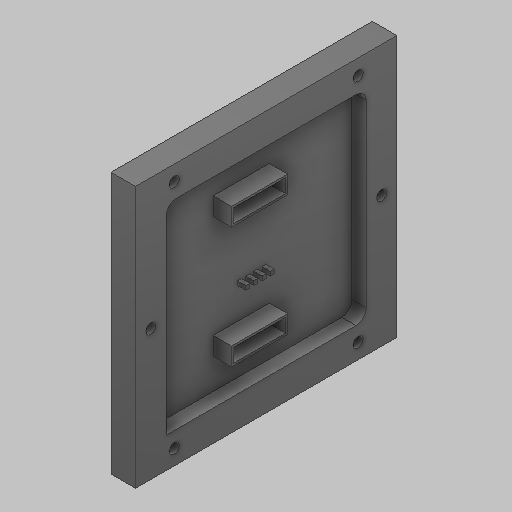
# Autodesk Inventor part: Pantalla_Led_B
Saved by Autodesk Inventor 2027 (Build 310192000, 192)
## iProperties
Created: 2026-11-23
Part Number: Pantalla_Led_B
Material: Genérico
Document SubType Name: Modeling
Designer: Alexander
Density: 1 g/cm^3
Appearance: Valor por defecto
Author: Alexander
Autodesk Inventor part; units mm, degrees
ref_plane "YZ Plane" through (0, 0, 0) normal (1, 0, 0) x (0, 1, 0)
ref_plane "XZ Plane" through (0, 0, 0) normal (0, 1, 0) x (-1, 0, 0)
ref_plane "XY Plane" through (0, 0, 0) normal (0, 0, 1) x (1, 0, 0)
sketch "Boceto1" plane through (0, 0, 0) normal (1, 0, 0) x (0, 1, 0)
  circle A0 centre (56.5, 45) radius 1.5
  circle A1 centre (-56.5, 45) radius 1.5
  circle A2 centre (-56.5, -45) radius 1.5
  circle A3 centre (56.5, -45) radius 1.5
  line L0 (64, 64) -> (-64, 64)
  line L1 (-64, 64) -> (-64, -64)
  line L2 (-64, -64) -> (64, -64)
  line L3 (64, -64) -> (64, 64)
  line L4 (44, 49) -> (-49, 49)
  line L5 (-49, 49) -> (-49, -44)
  line L6 (-44, -49) -> (44, -49)
  line L7 (49, -44) -> (49, 44)
  arc A4 (49, 44) -> (44, 49) centre (44, 44) ccw
  arc A5 (44, -49) -> (49, -44) centre (44, -44) ccw
  arc A6 (-49, -44) -> (-44, -49) centre (-44, -44) ccw
  circle A7 centre (0, 56.5) radius 1.5
  circle A8 centre (0, -56.5) radius 1.5
  circle A9 centre (56.5, 45) radius 2.5
  circle A10 centre (56.5, -45) radius 2.5
  circle A11 centre (0, -56.5) radius 2.5
  circle A12 centre (-56.5, -45) radius 2.5
  circle A13 centre (-56.5, 45) radius 2.5
  circle A14 centre (0, 56.5) radius 2.5
  line L8 (-25.2, 19) -> (-34, 19)
  line L9 (-34, 19) -> (-34, -8.5)
  line L10 (-34, -8.5) -> (-25.2, -8.5)
  line L11 (-25.2, -8.5) -> (-25.2, 19)
  line L12 (34, 19) -> (25.2, 19)
  line L13 (25.2, 19) -> (25.2, -8.5)
  line L14 (25.2, -8.5) -> (34, -8.5)
  line L15 (34, -8.5) -> (34, 19)
  line L16 (-4.8656, 9.0356) -> (-13.1244, 9.0356)
  line L17 (-13.1244, 9.0356) -> (-13.1244, -8.9644)
  line L18 (-13.1244, -8.9644) -> (-4.8656, -8.9644)
  line L19 (-4.8656, -8.9644) -> (-4.8656, 9.0356)
  line L20 (33, -7.5) -> (26.2, -7.5)
  line L21 (26.2, -7.5) -> (26.2, 18)
  line L22 (26.2, 18) -> (33, 18)
  line L23 (33, 18) -> (33, -7.5)
  line L24 (-26.2, -7.5) -> (-33, -7.5)
  line L25 (-33, -7.5) -> (-33, 18)
  line L26 (-33, 18) -> (-26.2, 18)
  line L27 (-26.2, 18) -> (-26.2, -7.5)
  line L28 (-8.0495, -6.9644) -> (-10.0495, -6.9644)
  line L29 (-10.0495, -6.9644) -> (-10.0495, -4.9644)
  line L30 (-10.0495, -4.9644) -> (-8.0495, -4.9644)
  line L31 (-8.0495, -4.9644) -> (-8.0495, -6.9644)
  line L32 (-8.0495, -2.9644) -> (-10.0495, -2.9644)
  line L33 (-10.0495, -2.9644) -> (-10.0495, -0.9644)
  line L34 (-10.0495, -0.9644) -> (-8.0495, -0.9644)
  line L35 (-8.0495, -0.9644) -> (-8.0495, -2.9644)
  line L36 (-8.0495, 1.0356) -> (-10.0495, 1.0356)
  line L37 (-10.0495, 1.0356) -> (-10.0495, 3.0356)
  line L38 (-10.0495, 3.0356) -> (-8.0495, 3.0356)
  line L39 (-8.0495, 3.0356) -> (-8.0495, 1.0356)
  line L40 (-8.0495, 5.0356) -> (-10.0495, 5.0356)
  line L41 (-10.0495, 5.0356) -> (-10.0495, 7.0356)
  line L42 (-10.0495, 7.0356) -> (-8.0495, 7.0356)
  line L43 (-8.0495, 7.0356) -> (-8.0495, 5.0356)
  point P0 (0, 0)
  point P1 (0, 0)
  point P2 (-49, 49)
  point P3 (49, 49)
  point P4 (49, -49)
  point P5 (-49, -49)
  point P6 (-8.995, -8.9644)
  point P7 (-9.0495, -0.9644)
  point P8 (-9.0495, -4.9644)
  dimension "d0" = 3
  dimension "d1" = 3
  dimension "d2" = 56.5
  dimension "d3" = 56.5
  dimension "d4" = 45
  dimension "d5" = 45
  dimension "d6" = 3
  dimension "d7" = 56.5
  dimension "d8" = 45
  dimension "d9" = 3
  dimension "d10" = 56.5
  dimension "d11" = 45
  dimension "d12" = 128
  dimension "d13" = 128
  dimension "d14" = 19
  dimension "d15" = 7.5
  dimension "d16" = 15
  dimension "d17" = 15
  dimension "d18" = 15
  dimension "d19" = 15
  dimension "d20" = 15
  dimension "d21" = 15
  dimension "d22" = 15
  dimension "d23" = 15
  dimension "d24" = 5
  dimension "d25" = 7.5
  dimension "d26" = 7.5
  dimension "d27" = 3
  dimension "d28" = 3
  dimension "d29" = 5
  dimension "d30" = 5
  dimension "d31" = 5
  dimension "d32" = 5
  dimension "d33" = 5
  dimension "d34" = 5
  dimension "d35" = 8.8
  dimension "d36" = 27.5
  dimension "d37" = 8.8
  dimension "d38" = 27.5
  dimension "d39" = 15
  dimension "d40" = 15
  dimension "d41" = 45
  dimension "d42" = 45
  dimension "d53" = 1
  dimension "d54" = 1
  dimension "d55" = 1
  dimension "d56" = 1
  dimension "d57" = 1
  dimension "d58" = 1
  dimension "d59" = 1
  dimension "d60" = 1
  dimension "d63" = 2
  dimension "d64" = 2
  dimension "d65" = 2
  dimension "d66" = 2
  dimension "d67" = 2
  dimension "d68" = 2
  dimension "d69" = 2
  dimension "d70" = 2
  dimension "d71" = 2
  dimension "d72" = 2
  dimension "d73" = 2
  dimension "d74" = 2
  dimension "d75" = 2
  constraints: 88 end point, 22 parallel, 15 centre point, 11 horizontal, 11 perpendicular, 9 coincident, 7 point on line, 6 point on circle, 6 tangent, 3 midpoint, 2 equal radius
  measures "d0" diameter of A0
  measures "d1" diameter of A1
  measures "d2" horizontal distance of point (0, 0) A0.centre
  measures "d3" horizontal distance of point (0, 0) A1.centre
  measures "d4" vertical distance of point (0, 0) A0.centre
  measures "d5" vertical distance of point (0, 0) A1.centre
  measures "d6" diameter of A2
  measures "d7" horizontal distance of point (0, 0) A2.centre
  measures "d8" vertical distance of point (0, 0) A2.centre
  measures "d9" diameter of A3
  measures "d10" horizontal distance of point (0, 0) A3.centre
  measures "d11" vertical distance of point (0, 0) A3.centre
  measures "d12" distance of L2.end L0.start
  measures "d13" distance of L0.start L0.end
  measures "d14" distance from line of L0 A1.centre
  measures "d15" distance from line of L1 A1.centre
  measures "d16" distance from line of L1 point (-49, -49)
  measures "d17" distance from line of point (-49, -49) L2
  measures "d18" distance from line of L0 point (-49, 49)
  measures "d19" distance from line of L1 point (-49, 49)
  measures "d20" distance from line of L0 point (49, 49)
  measures "d21" distance from line of L3 point (49, 49)
  measures "d22" distance from line of L3 point (49, -49)
  measures "d23" distance from line of point (49, -49) L2
  measures "d24" radius of A4
  measures "d25" distance from line of point (0, -56.5) L2
  measures "d26" distance from line of point (0, 56.5) L0
  measures "d27" diameter of A7
  measures "d28" diameter of A8
  measures "d29" diameter of A9
  measures "d30" diameter of A10
  measures "d31" diameter of A11
  measures "d32" diameter of A12
  measures "d33" diameter of A13
  measures "d34" diameter of A14
  measures "d35" distance of L10.end L9.end
  measures "d36" distance of L9.end L8.end
  measures "d37" distance of L14.end L13.end
  measures "d38" distance of L13.end L12.end
  measures "d39" distance between parallel lines of L5 L9
  measures "d40" distance between parallel lines of L15 L7
  measures "d41" distance between parallel lines of L0 L12
  measures "d42" distance between parallel lines of L0 L8
  measures "d53" distance between parallel lines of L23 L15
  measures "d54" distance between parallel lines of L14 L20
  measures "d55" distance between parallel lines of L13 L21
  measures "d56" distance between parallel lines of L22 L12
  measures "d57" distance between parallel lines of L26 L8
  measures "d58" distance between parallel lines of L9 L25
  measures "d59" distance between parallel lines of L27 L11
  measures "d60" distance between parallel lines of L10 L24
  measures "d63" distance of L29.end L30.end
  measures "d64" distance of L28.end L29.end
  measures "d65" distance of L33.end L34.end
  measures "d66" distance of L32.end L33.end
  measures "d67" distance of L37.end L38.end
  measures "d68" distance of L36.end L37.end
  measures "d69" distance of L41.end L42.end
  measures "d70" distance of L40.end L41.end
  measures "d71" distance from line of point (-8.995, -8.964) L28
  measures "d72" distance between parallel lines of L16 L42
  measures "d73" distance between parallel lines of L38 L40
  measures "d74" distance from line of point (-9.049, -0.964) L36
  measures "d75" distance from line of point (-9.049, -4.964) L32
extrude "Extrusión1" add sketch "Boceto1" along normal blind 12 contours L3 L2 L1 L0
extrude "Extrusión2" add sketch "Boceto1" along normal blind 5 contours A4 L7 A5 L6 A6 L5 L4
extrude "Extrusión3" add sketch "Boceto1" along normal blind 5 contours A0 | A9
extrude "Extrusión4" add sketch "Boceto1" along normal blind 5 contours A1 | A2 | A3 | A10 | A12 | A13
extrude "Extrusión5" add sketch "Boceto1" along normal blind 5 contours L11 L10 L9 L8 | L15 L14 L13 L12 | L19 L18 L17 L16 | L20 L21 L22 L23 | L24 L25 L26 L27 | L28 L29 L30 L31 | L32 L33 L34 L35 | L36 L37 L38 L39 | L40 L41 L42 L43
extrude "Extrusión6" add sketch "Boceto1" along normal blind 14 contours L11 L10 L9 L8 | L15 L14 L13 L12
extrude "Extrusión7" add sketch "Boceto1" along normal blind 9 contours L28 L29 L30 L31 | L32 L33 L34 L35 | L36 L37 L38 L39 | L40 L41 L42 L43
extrude "Extrusión8" add sketch "Boceto1" along normal blind 5 contours A7 | A14
extrude "Extrusión9" add sketch "Boceto1" along normal blind 5 contours A8 | A11
equation "\"d7\" = d3"
equation "\"d8\" = d5"
equation "\"d10\" = d2"
equation "\"d11\" = d4"
equation "\"d14\" = 0.5 * d13 - d5"
equation "\"d15\" = 0.5 * d13 - d3"
equation "\"d16\" = 2 * d15"
equation "\"d17\" = d16"
equation "\"d18\" = d16"
equation "\"d19\" = d16"
equation "\"d20\" = d18"
equation "\"d21\" = d18"
equation "\"d22\" = d21"
equation "\"d23\" = d20"
equation "\"d25\" = d15"
equation "\"d26\" = d15"
equation "\"d39\" = d16"
equation "\"d40\" = d22"
equation "\"d41\" = d4"
equation "\"d42\" = d41"
